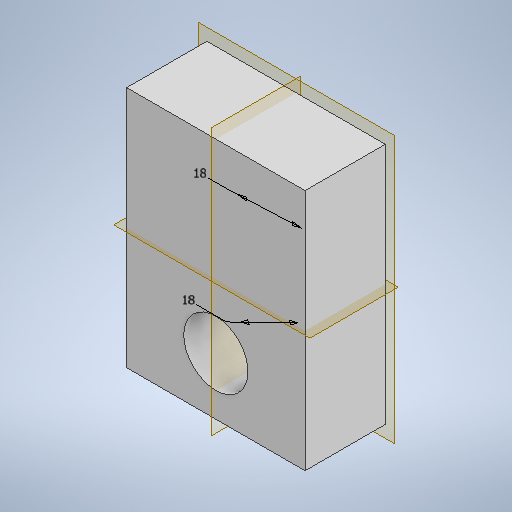
# Autodesk Inventor part: 00_Capot_arrière
Saved by Autodesk Inventor 2025.3 (Build 293356000, 356)
## iProperties
Created: 2026-11-05
Part Number: 00_Capot_arrière
Material: Générique
Document SubType Name: Modeling
Designer: hugoh
Density: 1 g/cm^3
Appearance: Par défaut
Author: hugoh
Autodesk Inventor part; units mm, degrees
sketch "Esquisse1" plane through (0, 0, 0) normal (0, 0, 1) x (1, 0, 0)
  line L0 (-25, 34) -> (25, 34)
  line L1 (25, 34) -> (25, -34)
  line L2 (25, -34) -> (-25, -34)
  line L3 (-25, -34) -> (-25, 34)
  line L4 (-25, 34) -> (25, -34) construction
  line L5 (25, 34) -> (-25, -34) construction
  point P0 (0, 0)
  dimension "d0" = 50
  dimension "d1" = 68
  constraints: 12 end point, 2 midpoint, 2 parallel, 1 horizontal, 1 perpendicular
  measures "d0" distance of L0.start L0.end
  measures "d1" distance of L0.end L1.end
extrude "Extrusion1" add sketch "Esquisse1" along normal blind 22.5
sketch "Esquisse2" plane through (0, 0, 0) normal (0, 0, 1) x (1, 0, 0)
  arc A0 (11.636, -7.2667) -> (-11.636, -7.2667) centre (0, 9) ccw
  arc A1 (-9.9997, -13.4167) -> (9.9997, -13.4167) centre (0, -18) ccw
  line L0 (0, 9) -> (0, -18) construction
  line L1 (0, 40.6) -> (0, -47.6) construction
  line L2 (-25, -34) -> (25, -34) projected
  arc A2 (-9.9997, -13.4167) -> (-11.636, -7.2667) centre (-14.5449, -11.3333) ccw
  arc A3 (11.636, -7.2667) -> (9.9997, -13.4167) centre (14.5449, -11.3333) ccw
  point P0 (0, 0)
  point P1 (0, -29)
  point P2 (0, 29)
  dimension "d4" = 40
  dimension "d5" = 22
  dimension "d6" = 27
  dimension "d8" = 5
  dimension "d9" = 63
  dimension "d10" = 5
  dimension "d11" = 5
  constraints: 10 point on circle, 4 centre point, 4 tangent, 2 end point, 1 collinear, 1 vertical
  measures "d4" diameter of A0
  measures "d5" diameter of A1
  measures "d6" distance of L0.end L0.start
  measures "d8" distance from line of L2 point (0, -29)
  measures "d9" distance from line of L2 point (0, 29)
  measures "d10" radius of A2
  measures "d11" radius of A3
extrude "Extrusion2" cut sketch "Esquisse2" along normal blind 7.5
sketch "Esquisse3" plane through (0, 0, 7.5) normal (0, 0, -1) x (-1, 0, 0)
  circle A0 centre (0, 9) radius 9
  circle A1 centre (0, -18) radius 9
  point P0 (0, 0)
  dimension "d14" = 18
  dimension "d15" = 18
  constraints: 2 centre point, 2 coincident
  measures "d14" diameter of A0
  measures "d15" diameter of A1
extrude "Extrusion3" cut sketch "Esquisse3" against normal through all contours A1
extrude "Extrusion4" cut sketch "Esquisse3" against normal blind 10 contours A0
